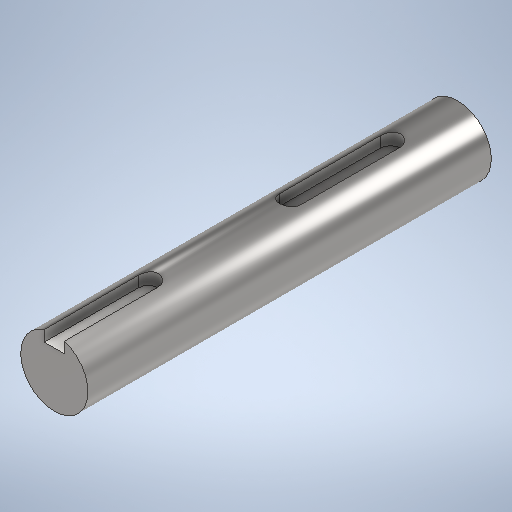
# Autodesk Inventor part: 00_Arbre_entree
Saved by Autodesk Inventor 2025.3 (Build 293356000, 356)
## iProperties
Created: 2026-11-06
Part Number: 00_Arbre_entree
Material: Acier, carbone
Document SubType Name: Modeling
Designer: hugoh
Density: 7.85 g/cm^3
Appearance: Semi-poli
Description: Arbre d'entrée du multiplicateur
Author: hugoh
Autodesk Inventor part; units mm, degrees
ref_plane "YZ Plane" through (0, 0, 0) normal (1, 0, 0) x (0, 1, 0)
ref_plane "XY Plane" through (0, 0, 0) normal (0, 0, 1) x (1, 0, 0)
derived "11_Squelette.ipt"
sketch "Pos_Axe_Engren" plane through (0, 0, 0) normal (0, 0, 1) x (1, 0, 0)
  line L0 (-35.41, 0) -> (35.41, 0) construction
  line L1 (0, 54.2716) -> (0, -9.0453) construction
  point P0 (0, 0)
  point P1 (0, 20)
  point P2 (0, 47)
ref_plane "Av_Engren" through (0, 0, 7.5) normal (0, 0, 1) x (1, 0, 0)
ref_plane "Arr_Engren" through (0, 0, -7.5) normal (0, 0, 1) x (1, 0, 0)
ref_plane "Fd_portee_roul_Av" through (0, 0, -17.5) normal (0, 0, 1) x (1, 0, 0)
ref_plane "Bout_input_shaft" through (0, 0, 42.5) normal (0, 0, 1) x (1, 0, 0)
ref_plane "Plan de construction1" through (0, 5, 0) normal (0, 1, 0) x (-1, 0, 0)
sketch "Esquisse5" plane through (0, 0, 0) normal (1, 0, 0) x (0, 1, 0)
  line L0 (5, -17.5) -> (0, -17.5)
  line L1 (0, -17.5) -> (0, 42.5)
  line L2 (0, 42.5) -> (5, 42.5)
  line L3 (5, 42.5) -> (5, -17.5)
  line L4 (-9.4, -17.5) -> (56.4, -17.5) construction
  line L5 (-9.4, 42.5) -> (56.4, 42.5) construction
  line L6 (5, 54.5) -> (5, -29.5) construction
  line L7 (0, -29.5) -> (0, 54.5) construction
  point P0 (0, 0)
  constraints: 8 end point, 4 collinear, 2 parallel, 1 horizontal, 1 perpendicular
revolve "Révolution2" add sketch "Esquisse5" angle 360 about axis through (0, 0, -10) along (0, 0, 1)
sketch "Esquisse6" plane through (0, 5, 0) normal (0, 1, 0) x (-1, 0, 0)
  line L0 (0, -7.5) -> (0, 7.5) construction
  line L1 (1.5, -7.5) -> (1.5, 7.5)
  line L2 (-1.5, 7.5) -> (-1.5, -7.5)
  arc A0 (-1.5, -7.5) -> (1.5, -7.5) centre (0, -7.5) ccw
  arc A1 (1.5, 7.5) -> (-1.5, 7.5) centre (0, 7.5) ccw
  line L3 (-12.238, 7.5) -> (12.238, 7.5) construction
  line L4 (-12.238, -7.5) -> (12.238, -7.5) construction
  line L5 (0, -29.5) -> (0, 54.5) construction
  line L6 (0, 42.5) -> (0, 28.5) construction
  line L7 (-1.5, 42.5) -> (-1.5, 28.5)
  line L8 (1.5, 28.5) -> (1.5, 42.5)
  arc A2 (1.5, 42.5) -> (-1.5, 42.5) centre (0, 42.5) ccw
  arc A3 (-1.5, 28.5) -> (1.5, 28.5) centre (0, 28.5) ccw
  line L9 (-7, 42.5) -> (7, 42.5) construction
  point P0 (0, 0)
  point P1 (0, 0)
  point P2 (0, 35.5)
  dimension "d15" = 3
  dimension "d16" = 14
  dimension "d17" = 3
  constraints: 16 end point, 8 point on circle, 8 tangent, 5 midpoint, 4 centre point, 2 collinear, 2 parallel, 2 vertical
  measures "d15" distance between parallel lines of L1 L2
  measures "d16" distance of L6.start L6.end
  measures "d17" distance between parallel lines of L8 L7
extrude "Extrusion1" cut sketch "Esquisse6" against normal blind 1.85
equation "\"d15\" = Larg_clav_shaft_in"
equation "\"d16\" = Long_clav_shaft_in"
equation "\"d17\" = Larg_clav_shaft_in"
equation "\"d0\" = 0.5 * Diam_input"
equation "\"Larg_clav_shaft_in\" = 3"
equation "\"Long_clav_shaft_in\" = 14"
equation "\"Diam_input\" = 10"
